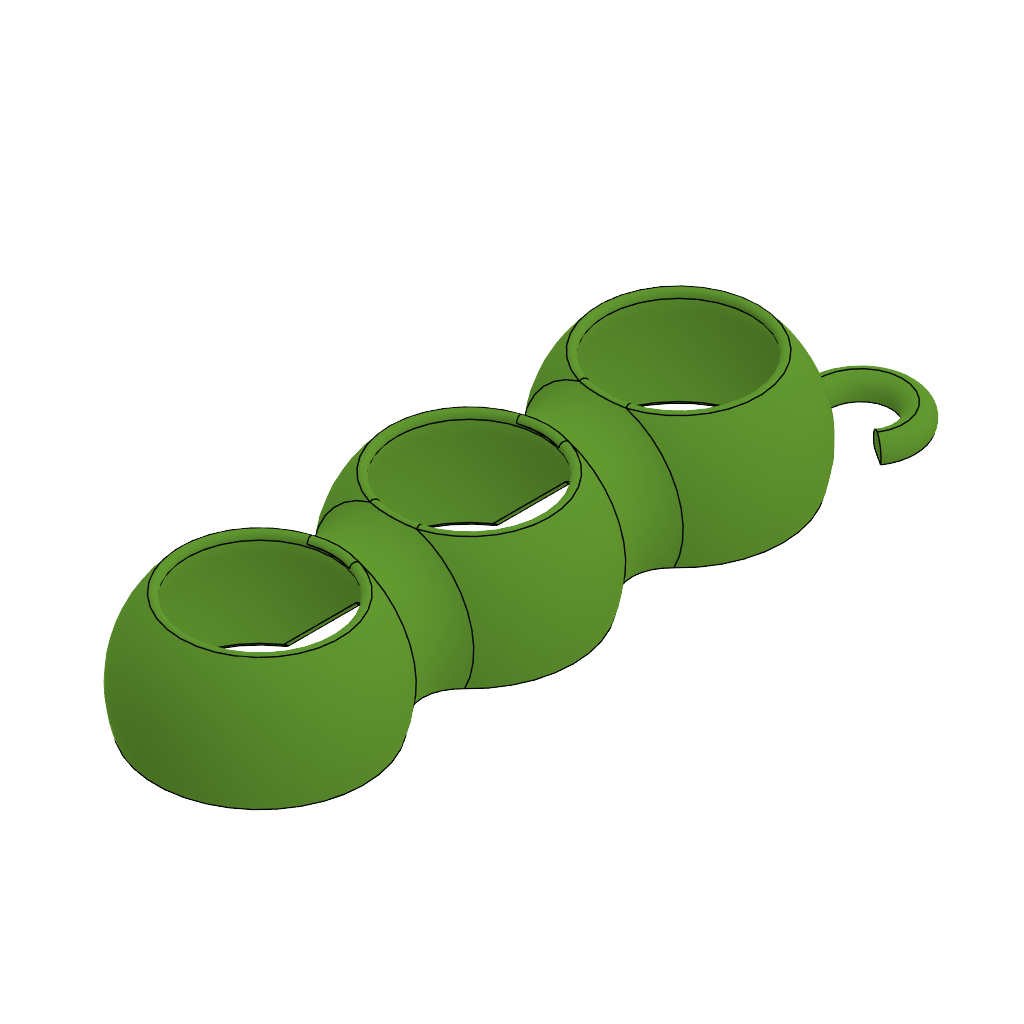
source (Autodesk Fusion 360 design; units mm, degrees)
part number: 2026-10-02-23-07-11-813
part number: 2026-10-02-23-07-24-127
Autodesk Fusion 360 part; units mm, degrees
sketch "Pod profile" plane through (0, 0, 0) normal (0, 1, 0) x (1, 0, 0)
  arc A0 (26.9117, -25.3922) -> (0, 37) centre (0, 0) ccw
  arc A1 (26.9117, -25.3922) -> (26.9117, -44.6078) centre (37.0945, -35) ccw
  arc A2 (26.9117, -95.3922) -> (26.9117, -44.6078) centre (0, -70) ccw
  arc A3 (26.9117, -95.3922) -> (26.9117, -114.6078) centre (37.0945, -105) ccw
  arc A4 (0, -177) -> (26.9117, -114.6078) centre (0, -140) ccw
  line L0 (0, -177) -> (0, 37)
revolve "Pod body" add sketch "Pod profile" angle 360 about axis through (0, 0, 1.75) along (0, 0, 1) makes body 1
ref_plane "WorkPlane1" through (0, 8.4891, 0) normal (0, 1, 0) x (0, 0, 1)
sketch "Sketch2" plane through (0, 8.4891, 0) normal (0, 1, 0) x (1, 0, 0)
  arc A0 (0, -184) -> (0, -168) centre (0, -176) ccw
  line L0 (0, -168) -> (0, -184)
revolve "Stem node" add sketch "Sketch2" angle 360 about axis through (0, 8.4891, 168) along (0, 0, 1) bodies 1
ref_plane "WorkPlane2" through (0, 10.0891, 0) normal (0, 1, 0) x (0, 0, 1)
sketch "Tendril path" plane through (0, 10.0891, 0) normal (0, 1, 0) x (1, 0, 0)
  spline S0 degree 5 poles (0, -169) (0.0136, -169.2974) (0.0382, -169.8949) (0.0676, -170.7987) (0.0916, -172.019) (0.0969, -173.5695) (0.0791, -175.1432) (0.0416, -176.7366) (-0.01, -178.3438) (-0.0671, -179.9556) (-0.1176, -181.5595) (-0.1475, -183.1416) (-0.1411, -184.6876) (-0.0823, -186.1854) (0.0446, -187.6254) (0.2543, -189.0037) (0.5591, -190.3211) (0.9687, -191.5812) (1.4898, -192.7873) (2.1248, -193.9409) (2.8715, -195.0384) (3.7233, -196.0708) (4.6701, -197.0262) (5.7001, -197.8915) (6.8009, -198.6542) (7.9607, -199.3052) (9.1692, -199.8388) (10.4165, -200.2523) (11.693, -200.5446) (12.9888, -200.7157) (14.2929, -200.7655) (15.5936, -200.6936) (16.8786, -200.5002) (18.1356, -200.1864) (19.3526, -199.7545) (20.5186, -199.2087) (21.6231, -198.5551) (22.6565, -197.801) (23.6098, -196.9542) (24.4744, -196.0232) (25.2421, -195.0161) (25.9055, -193.9414) (26.4579, -192.8083) (26.8943, -191.6276) (27.2111, -190.4117) (27.4068, -189.1753) (27.481, -187.9337) (27.4344, -186.7012) (27.268, -185.4905) (26.9828, -184.3101) (26.5797, -183.1653) (26.1633, -182.2798) (25.7983, -181.6331) (25.5315, -181.2097) (25.3923, -181) knots 0 0 0 0 0 0 0.02 0.04 0.06 0.08 0.1 0.12 0.14 0.16 0.18 0.2 0.22 0.24 0.26 0.28 0.3 0.32 0.34 0.36 0.38 0.4 0.42 0.44 0.46 0.48 0.5 0.52 0.54 0.56 0.58 0.6 0.62 0.64 0.66 0.68 0.7 0.72 0.74 0.76 0.78 0.8 0.82 0.84 0.86 0.88 0.9 0.92 0.94 0.96 0.98 1 1 1 1 1 1
  point P0 (0, -178)
  point P1 (0, -187)
  point P2 (1.8832, -193.4685)
  point P3 (6.3251, -198.3053)
  point P4 (12.2931, -200.6084)
  point P5 (18.4941, -200.04)
  point P6 (23.6539, -196.8679)
  point P7 (26.7795, -191.8792)
  point P8 (27.3485, -186.1906)
ref_plane "WorkPlane3" through (0, 10.0891, 169) normal (0.045595, 0, 0.99896) x (0, 1, 0)
sketch "Sketch4" plane through (0, 10.0891, 169) normal (0.045595, 0, 0.99896) x (0, 1, 0)
  circle A0 centre (0, 0) radius 4.5
sweep "Tendril hook" add profiles "Sketch4" path "Tendril path" along S0 section 1 bodies 1
sketch "Ball pockets" plane through (0, 0, 0) normal (0, 1, 0) x (1, 0, 0)
  arc A0 (0, -34) -> (0, 34) centre (0, 0) ccw
  line L0 (0, 34) -> (0, -34)
  arc A1 (0, -104) -> (0, -36) centre (0, -70) ccw
  line L1 (0, -36) -> (0, -104)
  arc A2 (0, -174) -> (0, -106) centre (0, -140) ccw
  line L2 (0, -106) -> (0, -174)
revolve "Ball pockets (1)" cut sketch "Ball pockets" angle 360 about axis through (0, 0, 1.75) along (0, 0, 1) bodies 1
ref_plane "WorkPlane4" through (0, 12.4891, 0) normal (0, 1, 0) x (0, 0, 1)
sketch "Front seam cut" plane through (0, 12.4891, 0) normal (0, 1, 0) x (1, 0, 0)
  line L0 (-70, 67) -> (70, 67)
  line L1 (70, 67) -> (70, -247)
  line L2 (70, -247) -> (-70, -247)
  line L3 (-70, -247) -> (-70, 67)
extrude "Front seam cut (1)" cut sketch "Front seam cut" along normal blind 80 bodies 1
sketch "Thumb windows" plane through (0, 0, 0) normal (0, 1, 0) x (1, 0, 0)
  circle A0 centre (0, 0) radius 24
  circle A1 centre (0, -70) radius 24
  circle A2 centre (0, -140) radius 24
extrude "Thumb windows (1)" cut sketch "Thumb windows" against normal blind 60 bodies 1
sketch "Seam groove" plane through (0, 0, 0) normal (0, 0, 1) x (1, 0, 0)
  line L0 (0, -5.5109) -> (21, 15.4891)
  line L1 (21, 15.4891) -> (-21, 15.4891)
  line L2 (-21, 15.4891) -> (0, -5.5109)
extrude "Seam groove (1)" cut sketch "Seam groove" along normal blind 140 bodies 1
chamfer "Lip lead-in chamfer" distance 1 angle 45 4 edges at (0, 12.4891, 171.6231) (-31.6231, 12.4891, 70) (0, 12.4891, -31.6231) (31.6231, 12.4891, 70) tangent chain off on bodies 1
fillet "Thumb window fillet" radius 1.5 6 edges at (-22.3759, -24.0832, -8.6788) (-22.3759, -28.1603, 8.6788) (-22.3759, -24.0832, 61.3212) (-22.3759, -28.1603, 78.6788) (-22.3759, -24.0832, 131.3212) (-22.3759, -28.1603, 148.6788) on bodies 1
fillet "Seam groove fillet" radius 1 18 edges at (17.5316, 12.0207, 42.8726) (17.5316, 12.0207, 27.1274) (8.9736, 3.4628, 32.6111) (0, -5.5109, 35) (8.9736, 3.4628, 37.3889) (-17.5316, 12.0207, 27.1274) (-17.5316, 12.0207, 42.8726) (-8.9736, 3.4628, 37.3889) (-8.9736, 3.4628, 32.6111) (-17.5316, 12.0207, 97.1274) (-17.5316, 12.0207, 112.8726) (-8.9736, 3.4628, 107.3889) (0, -5.5109, 105) (-8.9736, 3.4628, 102.6111) (17.5316, 12.0207, 97.1274) (8.9736, 3.4628, 102.6111) (8.9736, 3.4628, 107.3889) (17.5316, 12.0207, 112.8726) on bodies 1
fillet "Stem node fillet" radius 2.5 5 edges at (3.8262, 7.9584, 183.0056) (-4.0971, 7.9535, 182.8503) (-4.0971, 7.9535, 182.8503) (3.8262, 7.9584, 183.0056) (0, 0.5514, 176.9959) on bodies 1
sketch "Sketch1" plane through (0, 0, 0) normal (0, 1, 0) x (1, 0, 0) in component "Reference tennis balls"
  arc A0 (0, -33.5) -> (0, 33.5) centre (0, 0) ccw
  line L0 (0, 33.5) -> (0, -33.5)
  arc A1 (0, -103.5) -> (0, -36.5) centre (0, -70) ccw
  line L1 (0, -36.5) -> (0, -103.5)
  arc A2 (0, -173.5) -> (0, -106.5) centre (0, -140) ccw
  line L2 (0, -106.5) -> (0, -173.5)
revolve "Revolve1" add sketch "Sketch1" angle 360 about axis through (0, 0, 1.75) along (0, 0, 1) separate body makes body 2 at (31.7605, 7.9188, 7.1284) makes body 3 at (31.7605, 7.9188, 77.1284) makes body 4 at (31.7605, 7.9188, 147.1284) in component "Reference tennis balls"
move_body "Print orientation" bodies 1 to x (1, 0, 0) y (0, 0, -1) z (0, 1, 0) at (0, 0, 12.4891)
component "Reference tennis balls" placed x (1, 0, 0) y (0, 1, 0) z (0, 0, 1) at (0, 0, 0)
equation "ball_d = 67.0 mm" comment "measured tennis ball diameter"
equation "fit_clear = 1.0 mm" comment "pocket clearance over the ball"
equation "wall = 3.0 mm" comment "shell wall"
equation "web = 2.0 mm" comment "septum between balls"
equation "lip_open = 64.0 mm" comment "snap opening of the front seam"
equation "back_win_d = 48.0 mm" comment "thumb push-out window"
equation "tendril_d = 9.0 mm" comment "hanging hook tube"
equation "d29 = -( 60 mm )"
named bodies: "Pea pod", "Tennis ball 1", "Tennis ball 2", "Tennis ball 3"
